Display Board Button PCB (Autodesk Fusion 360 design; units mm, degrees)
part number: 2026-09-01-19-30-53-209
Autodesk Fusion 360 part; units mm, degrees
sketch "Sketch1" plane through (0, 0, 0) normal (0, 0, 1) x (1, 0, 0)
  line L0 (11.175, 52) -> (-11.175, 52)
  line L1 (-11.175, 52) -> (-11.175, -52)
  line L2 (-11.175, -52) -> (11.175, -52)
  line L3 (11.175, -52) -> (11.175, 52)
  line L4 (11.175, 52) -> (-11.175, -52) construction
  line L5 (-11.175, 52) -> (11.175, -52) construction
  circle A0 centre (-3.175, 42.5) radius 1.55
  line L6 (11.175, 0) -> (-11.175, 0) construction
  circle A1 centre (-3.175, -42.5) radius 1.55
  dimension "d1" = 22.35
  dimension "d2" = 104
  dimension "d5" = 3.1
  dimension "d6" = 9.5
  dimension "d7" = 8
  constraint horizontal L0
  constraint perpendicular L0 L1
  constraint parallel L0 L2
  constraint parallel L1 L3
  constraint coincident L4 origin
  constraint coincident L5 origin
  constraint midpoint L3 L6.start
  constraint midpoint L1 L6.end
  constraint symmetric A0 L6 A1
  measures "d1" distance of L1.end L2.end
  measures "d2" distance of L0.end L1.end
  measures "d5" diameter of A0
  measures "d6" distance of L0 A0.centre
  measures "d7" distance of L1 A0.centre
extrude "Extrude1" add sketch "Sketch1" along normal blind 1.6
sketch "Sketch2" plane through (0, 0, 1.6) normal (0, 0, 1) x (-1, 0, 0)
  circle A0 centre (3.175, -42.5) radius 1.55
  circle A1 centre (3.175, 42.5) radius 1.55
  line L0 (-11.175, 52) -> (-11.175, -52)
  line L1 (-11.175, -52) -> (11.175, -52)
  line L2 (11.175, -52) -> (11.175, 52)
  line L3 (11.175, 52) -> (-11.175, 52)
  line L4 (-1.675, -46) -> (-7.675, -46)
  line L5 (-7.675, -46) -> (-7.675, -40)
  line L6 (-7.675, -40) -> (-1.675, -40)
  line L7 (-1.675, -40) -> (-1.675, -46)
  line L8 (-7.675, -46) -> (-1.675, -40) construction
  circle A2 centre (-4.675, -43) radius 1.65
  line L9 (-1.675, -25) -> (-1.675, -31)
  line L10 (-7.675, -25) -> (-1.675, -25)
  circle A3 centre (-4.675, -28) radius 1.65
  line L11 (-7.675, -31) -> (-1.675, -25) construction
  line L12 (-1.675, -31) -> (-7.675, -31)
  line L13 (-7.675, -31) -> (-7.675, -25)
  line L14 (-1.675, -10) -> (-1.675, -16)
  line L15 (-7.675, -10) -> (-1.675, -10)
  circle A4 centre (-4.675, -13) radius 1.65
  line L16 (-7.675, -16) -> (-1.675, -10) construction
  line L17 (-1.675, -16) -> (-7.675, -16)
  line L18 (-7.675, -16) -> (-7.675, -10)
  line L19 (-1.675, 5) -> (-1.675, -1)
  line L20 (-7.675, 5) -> (-1.675, 5)
  circle A5 centre (-4.675, 2) radius 1.65
  line L21 (-7.675, -1) -> (-1.675, 5) construction
  line L22 (-1.675, -1) -> (-7.675, -1)
  line L23 (-7.675, -1) -> (-7.675, 5)
  line L24 (-1.675, 20) -> (-1.675, 14)
  line L25 (-7.675, 20) -> (-1.675, 20)
  circle A6 centre (-4.675, 17) radius 1.65
  line L26 (-7.675, 14) -> (-1.675, 20) construction
  line L27 (-1.675, 14) -> (-7.675, 14)
  line L28 (-7.675, 14) -> (-7.675, 20)
  line L29 (-1.675, 39) -> (-7.675, 39)
  line L30 (-7.675, 45) -> (-1.675, 45)
  line L31 (-7.675, 39) -> (-7.675, 45)
  line L32 (-7.675, 39) -> (-1.675, 45) construction
  line L33 (-1.675, 45) -> (-1.675, 39)
  circle A7 centre (-4.675, 42) radius 1.65
  line L34 (-4.675, 52) -> (-4.675, -52) construction
  circle A8 centre (-4.675, 32.1695) radius 1.5
  dimension "d8" = 6
  dimension "d9" = 6
  dimension "d10" = 3.5
  dimension "d11" = 6
  dimension "d12" = 3.3
  dimension "d15" = 0
  dimension "d16" = 15
  dimension "d17" = 3.5
  dimension "d18" = 7
  dimension "d19" = 3
  constraint horizontal L4
  constraint vertical L5
  constraint horizontal L6
  constraint vertical L7
  constraint midpoint L8 A2.centre
  constraint midpoint A7.centre L32
  constraint coincident L3 L34.start
  constraint coincident L1 L34.end
  constraint perpendicular L1 L34
  constraint coincident L34 A8.centre
  measures "d8" distance of L4.start L4.end
  measures "d9" distance of L4.start L6.end
  measures "d10" distance of L0 L5
  measures "d11" distance of L1 L4
  measures "d12" diameter of A2
  measures "d17" distance of L0 L31
  measures "d18" distance of L3 L30
  measures "d19" diameter of A8
extrude "Extrude2" add sketch "Sketch2" along normal blind 3.5 contours L4 L5 L6 L7 | L9 L10 L12 L13 | L14 L15 L17 L18 | L19 L20 L22 L23 | L24 L25 L27 L28 | L29 L30 L31 L33
extrude "Extrude3" add 6 faces at (5.1001, 43.43, 1.6) (4.4244, 27.3616, 1.6) (5.0843, 13.4561, 1.6) (4.2718, -1.5141, 1.6) (4.4244, -17.6384, 1.6) (5.1001, -41.57, 1.6) along direction (0, 0, 1) blind 4.5
extrude "Extrude4" add sketch "Sketch2" along normal blind 6.5 contours A8
fillet "Fillet1" radius 1.5 1 edges at (6.0735, -31.627, 8.1)
sketch "Sketch3" plane through (0, 0, 1.6) normal (0, 0, 1) x (-1, 0, 0)
  line L0 (-1.675, -40) -> (-1.675, -46)
  line L1 (-1.675, -46) -> (-7.675, -46)
  line L2 (-7.675, -46) -> (-7.675, -40)
  line L3 (-7.675, -40) -> (-1.675, -40)
  line L4 (-7.675, -1) -> (-7.675, 5)
  line L5 (-7.675, 5) -> (-1.675, 5)
  line L6 (-1.675, 5) -> (-1.675, -1)
  line L7 (-1.675, -1) -> (-7.675, -1)
  line L8 (-1.675, 45) -> (-1.675, 39)
  line L9 (-1.675, 39) -> (-7.675, 39)
  line L10 (-7.675, 39) -> (-7.675, 45)
  line L11 (-7.675, 45) -> (-1.675, 45)
  line L12 (-11.175, 52) -> (-11.175, -52)
  line L13 (-11.175, -52) -> (11.175, -52)
  line L14 (11.175, -52) -> (11.175, 52)
  line L15 (11.175, 52) -> (-11.175, 52)
  circle A0 centre (3.175, 42.5) radius 1.55
  circle A1 centre (3.175, -42.5) radius 1.55
  line L16 (-7.675, -16) -> (-7.675, -10)
  line L17 (-7.675, -10) -> (-1.675, -10)
  line L18 (-1.675, -10) -> (-1.675, -16)
  line L19 (-1.675, -16) -> (-7.675, -16)
  line L20 (-7.675, -31) -> (-7.675, -25)
  line L21 (-7.675, -25) -> (-1.675, -25)
  line L22 (-1.675, -25) -> (-1.675, -31)
  line L23 (-1.675, -31) -> (-7.675, -31)
  line L24 (-7.675, 14) -> (-7.675, 20)
  line L25 (-7.675, 20) -> (-1.675, 20)
  line L26 (-1.675, 20) -> (-1.675, 14)
  line L27 (-1.675, 14) -> (-7.675, 14)
  circle A2 centre (-4.675, 32.1695) radius 1.5
  line L28 (-11.175, 0) -> (11.175, 0) construction
  line L29 (3.675, -11) -> (11.175, -11)
  line L30 (11.175, -11) -> (11.175, 11)
  line L31 (11.175, 11) -> (3.675, 11)
  line L32 (3.675, 11) -> (3.675, -11)
  line L33 (3.675, -11) -> (11.175, 11) construction
  line L34 (11.175, -11) -> (3.675, 11) construction
  point P0 (7.425, 0)
  dimension "d28" = 7.5
  dimension "d29" = 22
  constraint midpoint L12 L28.start
  constraint midpoint L14 L28.end
  constraint horizontal L29
  constraint perpendicular L29 L30
  constraint parallel L29 L31
  constraint parallel L30 L32
  constraint coincident L33 P0
  constraint coincident L34 P0
  constraint coincident L28 P0
  constraint collinear L14 L30
  measures "d28" distance of L30.end L31.end
  measures "d29" distance of L29.end L30.end
extrude "Extrude5" add sketch "Sketch3" along normal blind 5 contours L14 L29 L30 L31 L32
sketch "Sketch4" plane through (-11.175, 0, 0) normal (-1, 0, 0) x (0, -1, 0)
  line L0 (-52, 0) -> (52, 0)
  line L1 (52, 0) -> (52, 1.6)
  line L2 (52, 1.6) -> (11, 1.6)
  line L3 (11, 1.6) -> (11, 6.6)
  line L4 (11, 6.6) -> (-11, 6.6)
  line L5 (-11, 6.6) -> (-11, 1.6)
  line L6 (-11, 1.6) -> (-52, 1.6)
  line L7 (-52, 1.6) -> (-52, 0)
  line L8 (-11, 1.6) -> (11, 1.6)
  constraint coincident L5.end L6.start
  constraint coincident L2.end L3.start
extrude "Extrude6" add sketch "Sketch4" along normal blind 0.75 contours L3 L4 L5 L8
equation "d22 = 3 mm + 1.5 mm"
